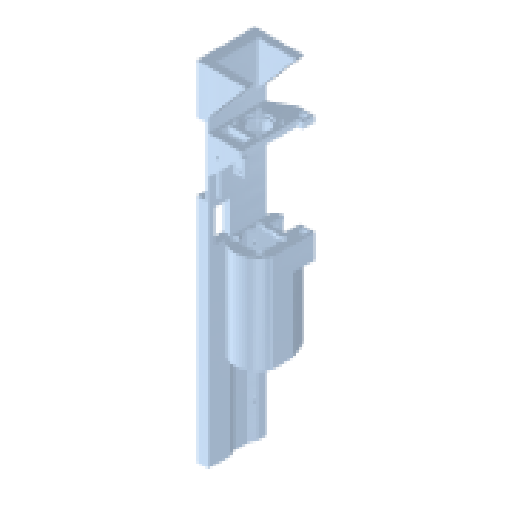
# Autodesk Inventor part: OT2-Pipette V0.7 - frame
Saved by Autodesk Inventor 2025.5 (Build 295498000, 498)
## iProperties
Created: 2026-11-20
Part Number: OT2-Pipette V0.7 - frame
Material: Generisch
Description: printed frame: mount wall with 3 M3 inserts, sleeve + ledge, header window, motor shelf, guide-rod column (PETG/ASA)
Document SubType Name: Modeling
Designer: benir
Density: 1 g/cm^3
Appearance: Light Steel Blue
Author: benir
Autodesk Inventor part; units mm, degrees
ref_plane "WP mount face" through (-9.5, 0, 0) normal (1, 0, 0) x (0, 1, 0)
ref_plane "WP pipette x" through (8.2, 0, 0) normal (1, 0, 0) x (0, 1, 0)
ref_plane "WP pipette z" through (0, 0, -3.46) normal (0, 0, 1) x (1, 0, 0)
ref_plane "WP motor seat" through (0, 123, 0) normal (0, 1, 0) x (-1, 0, 0)
ref_plane "y=ins_top_y" through (0, 46, 0) normal (0, 1, 0) x (-1, 0, 0)
ref_plane "z=ins_z" through (0, 0, 13.25) normal (0, 0, 1) x (1, 0, 0)
ref_plane "z=-ins_z" through (0, 0, -13.25) normal (0, 0, 1) x (1, 0, 0)
ref_plane "y=ins_bot_y" through (0, -43, 0) normal (0, 1, 0) x (-1, 0, 0)
sketch "mount wall" plane through (-9.5, 0, 0) normal (1, 0, 0) x (0, 1, 0)
  line L0 (-66, -18.75) -> (160.35, -18.75)
  line L1 (160.35, -18.75) -> (160.35, 18.75)
  line L2 (160.35, 18.75) -> (-66, 18.75)
  line L3 (-66, 18.75) -> (-66, -18.75)
  line L4 (0, -26.25) -> (0, 26.25) projected
  line L5 (-111.27, 0) -> (205.62, 0) projected
  point P0 (0, 0)
  dimension "d10" = 226.35
  dimension "d11" = 37.5
  dimension "d12" = 66
  dimension "d13" = 18.75
  constraints: 8 end point, 2 parallel, 1 horizontal, 1 perpendicular
  measures "d10" distance of L0.start L0.end
  measures "d11" distance of L2.end L0.start
  measures "d12" horizontal distance of point (0, 0) L2.end
  measures "d13" vertical distance of point (0, 0) L0.start
extrude "Extrusion2" add sketch "mount wall" along normal blind 7.3
fillet "wall top edges" radius 4 2 edges at (-5.85, 160.35, 18.75) (-5.85, 160.35, -18.75)
ref_plane "y=sleeve_y0" through (0, -6, 0) normal (0, 1, 0) x (-1, 0, 0)
sketch "sleeve outline" plane through (0, -6, 0) normal (0, 1, 0) x (-1, 0, 0)
  arc A0 (3.8, -0.6265) -> (-20.2, -0.6265) centre (-8.2, -3.46) ccw construction
  arc A1 (-15.2, -20.71) -> (-1.2, -20.71) centre (-8.2, -9.46) ccw construction
  line L0 (3.8, -0.6265) -> (3.8, -8.63) construction
  line L1 (3.8, -8.63) -> (1.58, -14.21) construction
  line L2 (1.58, -14.21) -> (-1.2, -20.71) construction
  line L3 (-15.2, -20.71) -> (-17.98, -14.21) construction
  line L4 (-17.98, -14.21) -> (-20.2, -8.63) construction
  line L5 (-20.2, -8.63) -> (-20.2, -0.6265) construction
  arc A2 (7.1, -0.2652) -> (-23.5, -0.2652) centre (-8.2, -3.46) ccw
  line L6 (7.1, -0.2652) -> (7.1, -9.2623)
  line L7 (7.1, -9.2623) -> (4.6307, -15.469)
  line L8 (4.6307, -15.469) -> (1.4503, -22.9053)
  arc A3 (-17.8503, -22.9053) -> (1.4503, -22.9053) centre (-8.2, -9.46) ccw
  line L9 (-17.8503, -22.9053) -> (-21.0307, -15.469)
  line L10 (-21.0307, -15.469) -> (-23.5, -9.2623)
  line L11 (-23.5, -9.2623) -> (-23.5, -0.2652)
  point P0 (0, 0)
  dimension "d18" = 3.46
  dimension "d19" = 8.2
  dimension "d20" = 9.46
  dimension "d21" = 8.2
  dimension "d22" = 0.6265
  dimension "d23" = 20.2
  dimension "d24" = 3.8
  dimension "d25" = 20.71
  dimension "d26" = 15.2
  dimension "d27" = 1.2
  dimension "d28" = 8.63
  dimension "d29" = 3.8
  dimension "d30" = 14.21
  dimension "d31" = 1.58
  dimension "d32" = 14.21
  dimension "d33" = 17.98
  dimension "d34" = 8.63
  dimension "d35" = 20.2
  dimension "d36" = 3.3
  constraints: 24 end point, 8 point on circle, 4 centre point, 7 other
  measures "d18" vertical distance of point (0, 0) A0.centre
  measures "d19" horizontal distance of point (0, 0) A0.centre
  measures "d20" vertical distance of point (0, 0) A1.centre
  measures "d21" horizontal distance of point (0, 0) A1.centre
  measures "d22" vertical distance of point (0, 0) L5.end
  measures "d23" horizontal distance of point (0, 0) L5.end
  measures "d24" horizontal distance of point (0, 0) L0.start
  measures "d25" vertical distance of point (0, 0) L3.start
  measures "d26" horizontal distance of point (0, 0) L3.start
  measures "d27" horizontal distance of point (0, 0) L2.end
  measures "d28" vertical distance of point (0, 0) L0.end
  measures "d29" horizontal distance of point (0, 0) L0.end
  measures "d30" vertical distance of point (0, 0) L1.end
  measures "d31" horizontal distance of point (0, 0) L1.end
  measures "d32" vertical distance of point (0, 0) L3.end
  measures "d33" horizontal distance of point (0, 0) L3.end
  measures "d34" vertical distance of point (0, 0) L4.end
  measures "d35" horizontal distance of point (0, 0) L4.end
  measures "d36" distance between parallel lines of L6 L0
extrude "sleeve and ledge" add sketch "sleeve outline" along normal blind 63.5
ref_plane "y=mot_front - shelf_t" through (0, 119, 0) normal (0, 1, 0) x (-1, 0, 0)
sketch "motor shelf" plane through (0, 119, 0) normal (0, 1, 0) x (-1, 0, 0)
  line L0 (2.7, -18.75) -> (-19.2, -18.75)
  line L1 (-19.2, -18.75) -> (-19.2, 18.75)
  line L2 (-19.2, 18.75) -> (2.7, 18.75)
  line L3 (2.7, 18.75) -> (2.7, -18.75)
  line L4 (0, -34.962) -> (0, 27.702) projected
  line L5 (16.1, 0) -> (-30.1, 0) projected
  point P0 (0, 0)
  dimension "d40" = 21.9
  dimension "d41" = 37.5
  dimension "d42" = 2.7
  dimension "d43" = 18.75
  constraints: 8 end point, 2 parallel, 1 horizontal, 1 perpendicular
  measures "d40" distance of L0.start L0.end
  measures "d41" distance of L2.end L0.start
  measures "d42" horizontal distance of point (0, 0) L2.end
  measures "d43" vertical distance of point (0, 0) L0.start
extrude "Extrusion4" add sketch "motor shelf" along normal blind 4
ref_plane "z=-env_z" through (0, 0, -18.75) normal (0, 0, 1) x (1, 0, 0)
sketch "gusset -z" plane through (0, 0, -18.75) normal (0, 0, 1) x (1, 0, 0)
  line L0 (-2.7, 119) -> (19.2, 119)
  line L1 (19.2, 119) -> (-2.7, 97.6)
  line L2 (-2.7, 97.6) -> (-2.7, 119)
  point P0 (0, 0)
  dimension "d47" = 119
  dimension "d48" = 2.7
  dimension "d49" = 119
  dimension "d50" = 19.2
  dimension "d51" = 97.6
  dimension "d52" = 2.7
  constraints: 6 end point
  measures "d47" vertical distance of point (0, 0) L0.start
  measures "d48" horizontal distance of point (0, 0) L0.start
  measures "d49" vertical distance of point (0, 0) L0.end
  measures "d50" horizontal distance of point (0, 0) L0.end
  measures "d51" vertical distance of point (0, 0) L1.end
  measures "d52" horizontal distance of point (0, 0) L1.end
extrude "Extrusion5" add sketch "gusset -z" along normal blind 2.5
ref_plane "z=env_z - gusset_t" through (0, 0, 16.25) normal (0, 0, 1) x (1, 0, 0)
sketch "gusset +z" plane through (0, 0, 16.25) normal (0, 0, 1) x (1, 0, 0)
  line L0 (-2.7, 119) -> (19.2, 119)
  line L1 (19.2, 119) -> (-2.7, 97.6)
  line L2 (-2.7, 97.6) -> (-2.7, 119)
  point P0 (0, 0)
  dimension "d56" = 119
  dimension "d57" = 2.7
  dimension "d58" = 119
  dimension "d59" = 19.2
  dimension "d60" = 97.6
  dimension "d61" = 2.7
  constraints: 6 end point
  measures "d56" vertical distance of point (0, 0) L0.start
  measures "d57" horizontal distance of point (0, 0) L0.start
  measures "d58" vertical distance of point (0, 0) L0.end
  measures "d59" horizontal distance of point (0, 0) L0.end
  measures "d60" vertical distance of point (0, 0) L1.end
  measures "d61" horizontal distance of point (0, 0) L1.end
extrude "Extrusion6" add sketch "gusset +z" along normal blind 2.5
ref_plane "y=col_y0" through (0, 42, 0) normal (0, 1, 0) x (-1, 0, 0)
sketch "rod column" plane through (0, 42, 0) normal (0, 1, 0) x (-1, 0, 0)
  line L0 (-15, -26.5) -> (-23.5, -26.5)
  line L1 (-23.5, -26.5) -> (-23.5, -17)
  line L2 (-23.5, -17) -> (-15, -17)
  line L3 (-15, -17) -> (-15, -26.5)
  line L4 (0, -35.55) -> (0, 27.8) projected
  line L5 (16.1, 0) -> (-30.1, 0) projected
  line L6 (-23.5, -9.2623) -> (-21.0307, -15.469) projected
  line L7 (-21.0307, -15.469) -> (-17.8503, -22.9053) projected
  line L8 (-23.5, -0.2652) -> (-23.5, -9.2623) projected
  line L9 (-23.5, -17) -> (-23.5, -9.2623)
  line L10 (-15, -26.5) -> (-12.404, -25.4672)
  arc A0 (-17.8503, -22.9053) -> (1.4503, -22.9053) centre (-8.2, -9.46) ccw projected
  point P0 (0, 0)
  point P1 (-15, -24.5485)
  point P2 (-20.3759, -17)
  dimension "d66" = 9.5
  dimension "d67" = 15
  dimension "d68" = 26.5
  dimension "d290" = 0
  constraints: 12 end point, 2 parallel, 1 horizontal, 1 perpendicular, 1 point on circle
  measures "d66" distance of L2.end L0.start
  measures "d67" horizontal distance of point (0, 0) L2.end
  measures "d68" vertical distance of point (0, 0) L0.start
  measures "d290" distance between parallel lines of L1 L8
extrude "guide rod column" add sketch "rod column" along normal blind 15.5
ref_plane "y=shelf_y0" through (0, 119, 0) normal (0, 1, 0) x (-1, 0, 0)
sketch "rod boss" plane through (0, 119, 0) normal (0, 1, 0) x (-1, 0, 0)
  line L0 (-14, -26.5) -> (-22.54, -26.5)
  line L1 (-22.54, -26.5) -> (-22.54, -17.75)
  line L2 (-22.54, -17.75) -> (-14, -17.75)
  line L3 (-14, -17.75) -> (-14, -26.5)
  line L4 (0, -35.55) -> (0, 27.8) projected
  line L5 (16.1, 0) -> (-30.1, 0) projected
  line L6 (-19.2, -18.75) -> (2.2, -18.75) projected
  line L7 (-14, -26.5) -> (0, -18.75)
  point P0 (0, 0)
  point P1 (-14, -18.75)
  dimension "d72" = 8.54
  dimension "d73" = 8.75
  dimension "d74" = 14
  dimension "d75" = 26.5
  constraints: 10 end point, 2 parallel, 2 point on line, 1 horizontal, 1 perpendicular
  measures "d72" distance of L0.start L0.end
  measures "d73" distance of L2.end L0.start
  measures "d74" horizontal distance of point (0, 0) L2.end
  measures "d75" vertical distance of point (0, 0) L0.start
extrude "guide rod boss" add sketch "rod boss" along normal blind 4
ref_plane "x=wall_x1 - cut_over" through (-3.2, 0, 0) normal (1, 0, 0) x (0, 1, 0)
sketch "rib" plane through (-3.2, 0, 0) normal (1, 0, 0) x (0, 1, 0)
  line L0 (84, 6.3) -> (119, 6.3)
  line L1 (119, 6.3) -> (119, 13.2)
  line L2 (119, 13.2) -> (84, 13.2)
  line L3 (84, 13.2) -> (84, 6.3)
  line L4 (0, -35.55) -> (0, 27.8) projected
  line L5 (-111.27, 0) -> (205.62, 0) projected
  point P0 (0, 0)
  dimension "d79" = 35
  dimension "d80" = 6.9
  dimension "d81" = 84
  dimension "d82" = 6.3
  constraints: 8 end point, 2 parallel, 1 horizontal, 1 perpendicular
  measures "d79" distance of L0.start L0.end
  measures "d80" distance of L2.end L0.start
  measures "d81" horizontal distance of point (0, 0) L2.end
  measures "d82" vertical distance of point (0, 0) L0.start
extrude "rib behind the top-block relief" add sketch "rib" along normal blind 3.2
ref_plane "y=body_bottom - body_cut_below" through (0, -96, 0) normal (0, 1, 0) x (-1, 0, 0)
sketch "body clearance outline" plane through (0, -96, 0) normal (0, 1, 0) x (-1, 0, 0)
  arc A0 (3.8, -0.6265) -> (-20.2, -0.6265) centre (-8.2, -3.46) ccw construction
  arc A1 (-15.2, -20.71) -> (-1.2, -20.71) centre (-8.2, -9.46) ccw construction
  line L0 (3.8, -0.6265) -> (3.8, -8.63) construction
  line L1 (3.8, -8.63) -> (1.58, -14.21) construction
  line L2 (1.58, -14.21) -> (-1.2, -20.71) construction
  line L3 (-15.2, -20.71) -> (-17.98, -14.21) construction
  line L4 (-17.98, -14.21) -> (-20.2, -8.63) construction
  line L5 (-20.2, -8.63) -> (-20.2, -0.6265) construction
  arc A2 (4.1, -0.5917) -> (-20.5, -0.5917) centre (-8.2, -3.46) ccw
  line L6 (4.1, -0.5917) -> (4.1, -8.6875)
  line L7 (4.1, -8.6875) -> (1.8573, -14.3245)
  line L8 (1.8573, -14.3245) -> (-0.9611, -20.9143)
  arc A3 (-15.4389, -20.9143) -> (-0.9611, -20.9143) centre (-8.2, -9.46) ccw
  line L9 (-15.4389, -20.9143) -> (-18.2573, -14.3245)
  line L10 (-18.2573, -14.3245) -> (-20.5, -8.6875)
  line L11 (-20.5, -8.6875) -> (-20.5, -0.5917)
  point P0 (0, 0)
  dimension "d86" = 3.46
  dimension "d87" = 8.2
  dimension "d88" = 9.46
  dimension "d89" = 8.2
  dimension "d90" = 0.6265
  dimension "d91" = 20.2
  dimension "d92" = 3.8
  dimension "d93" = 20.71
  dimension "d94" = 15.2
  dimension "d95" = 1.2
  dimension "d96" = 8.63
  dimension "d97" = 3.8
  dimension "d98" = 14.21
  dimension "d99" = 1.58
  dimension "d100" = 14.21
  dimension "d101" = 17.98
  dimension "d102" = 8.63
  dimension "d103" = 20.2
  dimension "d104" = 0.3
  constraints: 24 end point, 8 point on circle, 4 centre point, 7 other
  measures "d86" vertical distance of point (0, 0) A0.centre
  measures "d87" horizontal distance of point (0, 0) A0.centre
  measures "d88" vertical distance of point (0, 0) A1.centre
  measures "d89" horizontal distance of point (0, 0) A1.centre
  measures "d90" vertical distance of point (0, 0) L5.end
  measures "d91" horizontal distance of point (0, 0) L5.end
  measures "d92" horizontal distance of point (0, 0) L0.start
  measures "d93" vertical distance of point (0, 0) L3.start
  measures "d94" horizontal distance of point (0, 0) L3.start
  measures "d95" horizontal distance of point (0, 0) L2.end
  measures "d96" vertical distance of point (0, 0) L0.end
  measures "d97" horizontal distance of point (0, 0) L0.end
  measures "d98" vertical distance of point (0, 0) L1.end
  measures "d99" horizontal distance of point (0, 0) L1.end
  measures "d100" vertical distance of point (0, 0) L3.end
  measures "d101" horizontal distance of point (0, 0) L3.end
  measures "d102" vertical distance of point (0, 0) L4.end
  measures "d103" horizontal distance of point (0, 0) L4.end
  measures "d104" distance between parallel lines of L6 L0
extrude "body clearance" cut sketch "body clearance outline" along normal blind 151
ref_plane "y=body_top - cut_over" through (0, 54, 0) normal (0, 1, 0) x (-1, 0, 0)
sketch "knob hole" plane through (0, 54, 0) normal (0, 1, 0) x (-1, 0, 0)
  circle A0 centre (-8.2, -3.46) radius 9.1
  point P0 (0, 0)
  dimension "d108" = 3.46
  dimension "d109" = 8.2
  dimension "d110" = 18.2
  constraints: 1 centre point
  measures "d108" vertical distance of point (0, 0) A0.centre
  measures "d109" horizontal distance of point (0, 0) A0.centre
  measures "d110" diameter of A0
extrude "Extrusion11" cut sketch "knob hole" along normal blind 4.5
ref_plane "y=sleeve_y0 - cut_over" through (0, -7, 0) normal (0, 1, 0) x (-1, 0, 0)
sketch "ejector slot" plane through (0, -7, 0) normal (0, 1, 0) x (-1, 0, 0)
  line L0 (-2.6, -26.5) -> (-13.8, -26.5)
  line L1 (-13.8, -26.5) -> (-13.8, -15.26)
  line L2 (-13.8, -15.26) -> (-2.6, -15.26)
  line L3 (-2.6, -15.26) -> (-2.6, -26.5)
  line L4 (0, -35.55) -> (0, 27.8) projected
  line L5 (16.1, 0) -> (-30.1, 0) projected
  point P0 (0, 0)
  dimension "d114" = 11.2
  dimension "d115" = 11.24
  dimension "d116" = 2.6
  dimension "d117" = 26.5
  constraints: 8 end point, 2 parallel, 1 horizontal, 1 perpendicular
  measures "d114" distance of L0.start L0.end
  measures "d115" distance of L2.end L0.start
  measures "d116" horizontal distance of point (0, 0) L2.end
  measures "d117" vertical distance of point (0, 0) L0.start
extrude "ejector button slot" cut sketch "ejector slot" along normal blind 62
ref_plane "y=body_top - eject_win_h" through (0, 27, 0) normal (0, 1, 0) x (-1, 0, 0)
sketch "eject window" plane through (0, 27, 0) normal (0, 1, 0) x (-1, 0, 0)
  line L0 (-3.2, -26.5) -> (-13.2, -26.5)
  line L1 (-13.2, -26.5) -> (-13.2, -15.46)
  line L2 (-13.2, -15.46) -> (-3.2, -15.46)
  line L3 (-3.2, -15.46) -> (-3.2, -26.5)
  line L4 (0, -35.55) -> (0, 27.8) projected
  line L5 (16.1, 0) -> (-30.1, 0) projected
  point P0 (0, 0)
  dimension "d121" = 10
  dimension "d122" = 11.04
  dimension "d123" = 3.2
  dimension "d124" = 26.5
  constraints: 8 end point, 2 parallel, 1 horizontal, 1 perpendicular
  measures "d121" distance of L0.start L0.end
  measures "d122" distance of L2.end L0.start
  measures "d123" horizontal distance of point (0, 0) L2.end
  measures "d124" vertical distance of point (0, 0) L0.start
extrude "Extrusion13" cut sketch "eject window" along normal blind 31.5
sketch "ledge relief" plane through (0, 54, 0) normal (0, 1, 0) x (-1, 0, 0)
  line L0 (-0.5, -11.96) -> (-15.9, -11.96)
  line L1 (-15.9, -11.96) -> (-15.9, -3.46)
  line L2 (-15.9, -3.46) -> (-0.5, -3.46)
  line L3 (-0.5, -3.46) -> (-0.5, -11.96)
  line L4 (0, -35.55) -> (0, 27.8) projected
  line L5 (16.1, 0) -> (-30.1, 0) projected
  point P0 (0, 0)
  dimension "d127" = 15.4
  dimension "d128" = 8.5
  dimension "d129" = 0.5
  dimension "d130" = 11.96
  constraints: 8 end point, 2 parallel, 1 horizontal, 1 perpendicular
  measures "d127" distance of L0.start L0.end
  measures "d128" distance of L2.end L0.start
  measures "d129" horizontal distance of point (0, 0) L2.end
  measures "d130" vertical distance of point (0, 0) L0.start
extrude "Extrusion14" cut sketch "ledge relief" along normal blind 4.5
ref_plane "y=rod_y0 - 0.5 mm" through (0, 47.5, 0) normal (0, 1, 0) x (-1, 0, 0)
sketch "guide rod hole" plane through (0, 47.5, 0) normal (0, 1, 0) x (-1, 0, 0)
  circle A0 centre (-18.5, -22) radius 2.5
  point P0 (0, 0)
  dimension "d134" = 22
  dimension "d135" = 18.5
  dimension "d136" = 5
  constraints: 1 centre point
  measures "d134" vertical distance of point (0, 0) A0.centre
  measures "d135" horizontal distance of point (0, 0) A0.centre
  measures "d136" diameter of A0
extrude "Extrusion15" cut sketch "guide rod hole" along normal blind 76.5
ref_plane "y=body_bottom - cut_over" through (0, -67, 0) normal (0, 1, 0) x (-1, 0, 0)
sketch "seat insert holes" plane through (0, -67, 0) normal (0, 1, 0) x (-1, 0, 0)
  circle A0 centre (5.85, 13.5) radius 2.05
  circle A1 centre (5.85, -16) radius 2.05
  point P0 (0, 0)
  dimension "d140" = 13.5
  dimension "d141" = 5.85
  dimension "d142" = 4.1
  dimension "d143" = 16
  dimension "d144" = 5.85
  dimension "d145" = 4.1
  constraints: 2 centre point
  measures "d140" vertical distance of point (0, 0) A0.centre
  measures "d141" horizontal distance of point (0, 0) A0.centre
  measures "d142" diameter of A0
  measures "d143" vertical distance of point (0, 0) A1.centre
  measures "d144" horizontal distance of point (0, 0) A1.centre
  measures "d145" diameter of A1
extrude "M3 inserts for the pipette seat" cut sketch "seat insert holes" along normal blind 6.7
ref_plane "x=mount_x - cut_over" through (-10.5, 0, 0) normal (1, 0, 0) x (0, 1, 0)
sketch "insert holes" plane through (-10.5, 0, 0) normal (1, 0, 0) x (0, 1, 0)
  circle A0 centre (46, 13.25) radius 2.05
  circle A1 centre (46, -13.25) radius 2.05
  circle A2 centre (-43, -13.25) radius 2.05
  point P0 (0, 0)
  dimension "d149" = 13.25
  dimension "d150" = 46
  dimension "d151" = 4.1
  dimension "d152" = 13.25
  dimension "d153" = 46
  dimension "d154" = 4.1
  dimension "d155" = 13.25
  dimension "d156" = 43
  dimension "d157" = 4.1
  constraints: 3 centre point
  measures "d149" vertical distance of point (0, 0) A0.centre
  measures "d150" horizontal distance of point (0, 0) A0.centre
  measures "d151" diameter of A0
  measures "d152" vertical distance of point (0, 0) A1.centre
  measures "d153" horizontal distance of point (0, 0) A1.centre
  measures "d154" diameter of A1
  measures "d155" vertical distance of point (0, 0) A2.centre
  measures "d156" horizontal distance of point (0, 0) A2.centre
  measures "d157" diameter of A2
extrude "Extrusion17" cut sketch "insert holes" along normal blind 7.7
sketch "insert recesses" plane through (-10.5, 0, 0) normal (1, 0, 0) x (0, 1, 0)
  circle A0 centre (46, 13.25) radius 3
  circle A1 centre (46, -13.25) radius 3
  circle A2 centre (-43, -13.25) radius 3
  point P0 (0, 0)
  dimension "d160" = 13.25
  dimension "d161" = 46
  dimension "d162" = 6
  dimension "d163" = 13.25
  dimension "d164" = 46
  dimension "d165" = 6
  dimension "d166" = 13.25
  dimension "d167" = 43
  dimension "d168" = 6
  constraints: 3 centre point
  measures "d160" vertical distance of point (0, 0) A0.centre
  measures "d161" horizontal distance of point (0, 0) A0.centre
  measures "d162" diameter of A0
  measures "d163" vertical distance of point (0, 0) A1.centre
  measures "d164" horizontal distance of point (0, 0) A1.centre
  measures "d165" diameter of A1
  measures "d166" vertical distance of point (0, 0) A2.centre
  measures "d167" horizontal distance of point (0, 0) A2.centre
  measures "d168" diameter of A2
extrude "Extrusion18" cut sketch "insert recesses" along normal blind 1.3
sketch "grub screw holes" plane through (-10.5, 0, 0) normal (1, 0, 0) x (0, 1, 0)
  circle A0 centre (4, -3.46) radius 1.25
  circle A1 centre (42, -3.46) radius 1.25
  point P0 (0, 0)
  dimension "d171" = 3.46
  dimension "d172" = 4
  dimension "d173" = 2.5
  dimension "d174" = 3.46
  dimension "d175" = 42
  dimension "d176" = 2.5
  constraints: 2 centre point
  measures "d171" vertical distance of point (0, 0) A0.centre
  measures "d172" horizontal distance of point (0, 0) A0.centre
  measures "d173" diameter of A0
  measures "d174" vertical distance of point (0, 0) A1.centre
  measures "d175" horizontal distance of point (0, 0) A1.centre
  measures "d176" diameter of A1
extrude "M3 grub screw holes" cut sketch "grub screw holes" along normal blind 7.7
ref_plane "y=mot_front - mot_pilot_h - pilot_clr" through (0, 121.1, 0) normal (0, 1, 0) x (-1, 0, 0)
sketch "motor pilot recess" plane through (0, 121.1, 0) normal (0, 1, 0) x (-1, 0, 0)
  circle A0 centre (-8.2, -3.46) radius 8.2
  point P0 (0, 0)
  dimension "d180" = 3.46
  dimension "d181" = 8.2
  dimension "d182" = 16.4
  constraints: 1 centre point
  measures "d180" vertical distance of point (0, 0) A0.centre
  measures "d181" horizontal distance of point (0, 0) A0.centre
  measures "d182" diameter of A0
extrude "Extrusion20" cut sketch "motor pilot recess" along normal blind 2.9
ref_plane "y=mot_front - shelf_t - cut_over" through (0, 118, 0) normal (0, 1, 0) x (-1, 0, 0)
sketch "motor boss hole" plane through (0, 118, 0) normal (0, 1, 0) x (-1, 0, 0)
  circle A0 centre (-8.2, -3.46) radius 6.9
  point P0 (0, 0)
  dimension "d186" = 3.46
  dimension "d187" = 8.2
  dimension "d188" = 13.8
  constraints: 1 centre point
  measures "d186" vertical distance of point (0, 0) A0.centre
  measures "d187" horizontal distance of point (0, 0) A0.centre
  measures "d188" diameter of A0
extrude "Extrusion21" cut sketch "motor boss hole" along normal blind 6
sketch "motor screw holes" plane through (0, 118, 0) normal (0, 1, 0) x (-1, 0, 0)
  circle A0 centre (-0.5, -11.16) radius 1.2
  circle A1 centre (-0.5, 4.24) radius 1.2
  circle A2 centre (-15.9, -11.16) radius 1.2
  circle A3 centre (-15.9, 4.24) radius 1.2
  point P0 (0, 0)
  dimension "d191" = 11.16
  dimension "d192" = 0.5
  dimension "d193" = 2.4
  dimension "d194" = 4.24
  dimension "d195" = 0.5
  dimension "d196" = 2.4
  dimension "d197" = 11.16
  dimension "d198" = 15.9
  dimension "d199" = 2.4
  dimension "d200" = 4.24
  dimension "d201" = 15.9
  dimension "d202" = 2.4
  constraints: 4 centre point
  measures "d191" vertical distance of point (0, 0) A0.centre
  measures "d192" horizontal distance of point (0, 0) A0.centre
  measures "d193" diameter of A0
  measures "d194" vertical distance of point (0, 0) A1.centre
  measures "d195" horizontal distance of point (0, 0) A1.centre
  measures "d196" diameter of A1
  measures "d197" vertical distance of point (0, 0) A2.centre
  measures "d198" horizontal distance of point (0, 0) A2.centre
  measures "d199" diameter of A2
  measures "d200" vertical distance of point (0, 0) A3.centre
  measures "d201" horizontal distance of point (0, 0) A3.centre
  measures "d202" diameter of A3
extrude "4 x M2 motor screw holes" cut sketch "motor screw holes" along normal blind 6
sketch "screwdriver channels" plane through (0, 54, 0) normal (0, 1, 0) x (-1, 0, 0)
  circle A0 centre (-0.5, -11.16) radius 2.2
  circle A1 centre (-0.5, 4.24) radius 2.2
  circle A2 centre (-15.9, -11.16) radius 2.2
  circle A3 centre (-15.9, 4.24) radius 2.2
  point P0 (0, 0)
  dimension "d205" = 11.16
  dimension "d206" = 0.5
  dimension "d207" = 4.4
  dimension "d208" = 4.24
  dimension "d209" = 0.5
  dimension "d210" = 4.4
  dimension "d211" = 11.16
  dimension "d212" = 15.9
  dimension "d213" = 4.4
  dimension "d214" = 4.24
  dimension "d215" = 15.9
  dimension "d216" = 4.4
  constraints: 4 centre point
  measures "d205" vertical distance of point (0, 0) A0.centre
  measures "d206" horizontal distance of point (0, 0) A0.centre
  measures "d207" diameter of A0
  measures "d208" vertical distance of point (0, 0) A1.centre
  measures "d209" horizontal distance of point (0, 0) A1.centre
  measures "d210" diameter of A1
  measures "d211" vertical distance of point (0, 0) A2.centre
  measures "d212" horizontal distance of point (0, 0) A2.centre
  measures "d213" diameter of A2
  measures "d214" vertical distance of point (0, 0) A3.centre
  measures "d215" horizontal distance of point (0, 0) A3.centre
  measures "d216" diameter of A3
extrude "Extrusion23" cut sketch "screwdriver channels" along normal blind 66
sketch "plug pocket" plane through (-10.5, 0, 0) normal (1, 0, 0) x (0, 1, 0)
  line L0 (54, 1) -> (83, 1)
  line L1 (83, 1) -> (83, 17.6)
  line L2 (83, 17.6) -> (54, 17.6)
  line L3 (54, 17.6) -> (54, 1)
  line L4 (0, -35.55) -> (0, 27.8) projected
  line L5 (-111.27, 0) -> (205.62, 0) projected
  point P0 (0, 0)
  dimension "d219" = 29
  dimension "d220" = 16.6
  dimension "d221" = 54
  dimension "d222" = 1
  constraints: 8 end point, 2 parallel, 1 horizontal, 1 perpendicular
  measures "d219" distance of L0.start L0.end
  measures "d220" distance of L2.end L0.start
  measures "d221" horizontal distance of point (0, 0) L2.end
  measures "d222" vertical distance of point (0, 0) L0.start
extrude "pocket for the robot's plug holder" cut sketch "plug pocket" along normal blind 3.5
sketch "header window" plane through (-10.5, 0, 0) normal (1, 0, 0) x (0, 1, 0)
  line L0 (57.9, 4.45) -> (79.1, 4.45)
  line L1 (79.1, 4.45) -> (79.1, 14.15)
  line L2 (79.1, 14.15) -> (57.9, 14.15)
  line L3 (57.9, 14.15) -> (57.9, 4.45)
  line L4 (0, -35.55) -> (0, 27.8) projected
  line L5 (-111.27, 0) -> (205.62, 0) projected
  point P0 (0, 0)
  dimension "d225" = 21.2
  dimension "d226" = 9.7
  dimension "d227" = 57.9
  dimension "d228" = 4.45
  constraints: 8 end point, 2 parallel, 1 horizontal, 1 perpendicular
  measures "d225" distance of L0.start L0.end
  measures "d226" distance of L2.end L0.start
  measures "d227" horizontal distance of point (0, 0) L2.end
  measures "d228" vertical distance of point (0, 0) L0.start
extrude "2x5 header window" cut sketch "header window" along normal blind 9.3
ref_plane "z=brd_z_front" through (0, 0, 15.35) normal (0, 0, 1) x (1, 0, 0)
sketch "XIAO pin clearance" plane through (0, 0, 15.35) normal (0, 0, 1) x (1, 0, 0)
  line L0 (-0.2, 88.5) -> (22.8, 88.5)
  line L1 (22.8, 88.5) -> (22.8, 109.5)
  line L2 (22.8, 109.5) -> (-0.2, 109.5)
  line L3 (-0.2, 109.5) -> (-0.2, 88.5)
  line L4 (0, -111.27) -> (0, 205.62) projected
  line L5 (-16.1, 0) -> (30.1, 0) projected
  point P0 (0, 0)
  dimension "d238" = 23
  dimension "d239" = 21
  dimension "d240" = 0.2
  dimension "d241" = 88.5
  constraints: 8 end point, 2 parallel, 1 horizontal, 1 perpendicular
  measures "d238" distance of L0.start L0.end
  measures "d239" distance of L2.end L0.start
  measures "d240" horizontal distance of point (0, 0) L2.end
  measures "d241" vertical distance of point (0, 0) L0.start
extrude "Extrusion27" cut sketch "XIAO pin clearance" along normal blind 1.8
sketch "board tabs" plane through (0, 0, 15.35) normal (0, 0, 1) x (1, 0, 0)
  line L0 (14.8, 108.8) -> (20.8, 108.8)
  line L1 (20.8, 108.8) -> (20.8, 119.5)
  line L2 (20.8, 119.5) -> (14.8, 119.5)
  line L3 (14.8, 119.5) -> (14.8, 108.8)
  line L4 (0, -111.27) -> (0, 205.62) projected
  line L5 (-16.1, 0) -> (30.1, 0) projected
  line L6 (1.2, 108.8) -> (7.2, 108.8)
  line L7 (7.2, 108.8) -> (7.2, 119.5)
  line L8 (7.2, 119.5) -> (1.2, 119.5)
  line L9 (1.2, 119.5) -> (1.2, 108.8)
  point P0 (0, 0)
  dimension "d244" = 6
  dimension "d245" = 10.7
  dimension "d246" = 14.8
  dimension "d247" = 108.8
  dimension "d248" = 6
  dimension "d249" = 10.7
  dimension "d250" = 1.2
  dimension "d251" = 108.8
  constraints: 16 end point, 4 parallel, 2 horizontal, 2 perpendicular
  measures "d244" distance of L0.start L0.end
  measures "d245" distance of L2.end L0.start
  measures "d246" horizontal distance of point (0, 0) L2.end
  measures "d247" vertical distance of point (0, 0) L0.start
  measures "d248" distance of L6.start L6.end
  measures "d249" distance of L8.end L6.start
  measures "d250" horizontal distance of point (0, 0) L8.end
  measures "d251" vertical distance of point (0, 0) L6.start
extrude "Extrusion28" add sketch "board tabs" along normal blind 3.4
ref_plane "z=brd_z_front - cut_over" through (0, 0, 14.35) normal (0, 0, 1) x (1, 0, 0)
sketch "board screw holes" plane through (0, 0, 14.35) normal (0, 0, 1) x (1, 0, 0)
  circle A0 centre (17.8, 111.8) radius 0.9
  circle A1 centre (4.2, 111.8) radius 0.9
  point P0 (0, 0)
  dimension "d255" = 111.8
  dimension "d256" = 17.8
  dimension "d257" = 1.8
  dimension "d258" = 111.8
  dimension "d259" = 4.2
  dimension "d260" = 1.8
  constraints: 2 centre point
  measures "d255" vertical distance of point (0, 0) A0.centre
  measures "d256" horizontal distance of point (0, 0) A0.centre
  measures "d257" diameter of A0
  measures "d258" vertical distance of point (0, 0) A1.centre
  measures "d259" horizontal distance of point (0, 0) A1.centre
  measures "d260" diameter of A1
extrude "tool board M2 holes" cut sketch "board screw holes" along normal blind 5.4
ref_plane "x=wall_x1 + cut_over" through (-1.2, 0, 0) normal (1, 0, 0) x (0, 1, 0)
sketch "switch screw holes" plane through (-1.2, 0, 0) normal (1, 0, 0) x (0, 1, 0)
  circle A0 centre (111.3, -12.85) radius 0.9
  circle A1 centre (111.3, -6.35) radius 0.9
  point P0 (0, 0)
  dimension "d264" = 12.85
  dimension "d265" = 111.3
  dimension "d266" = 1.8
  dimension "d267" = 6.35
  dimension "d268" = 111.3
  dimension "d269" = 1.8
  constraints: 2 centre point
  measures "d264" vertical distance of point (0, 0) A0.centre
  measures "d265" horizontal distance of point (0, 0) A0.centre
  measures "d266" diameter of A0
  measures "d267" vertical distance of point (0, 0) A1.centre
  measures "d268" horizontal distance of point (0, 0) A1.centre
  measures "d269" diameter of A1
extrude "Extrusion30" cut sketch "switch screw holes" against normal blind 7
sketch "GEN2 outline trim" plane through (0, -67, 0) normal (0, 1, 0) x (-1, 0, 0)
  line L0 (59.5, -75.5) -> (-72.84, -75.5)
  line L1 (-72.84, -75.5) -> (-72.84, 68.75)
  line L2 (-72.84, 68.75) -> (59.5, 68.75)
  line L3 (59.5, 68.75) -> (59.5, -75.5)
  line L4 (0, -104.35) -> (0, 97.6) projected
  line L5 (85.968, 0) -> (-99.308, 0) projected
  line L6 (9.5, -25.5) -> (-22.84, -25.5)
  line L7 (-22.84, -25.5) -> (-22.84, 18.75)
  line L8 (-22.84, 18.75) -> (9.5, 18.75)
  line L9 (9.5, 18.75) -> (9.5, -25.5)
  point P0 (0, 0)
  dimension "d272" = 132.34
  dimension "d273" = 144.25
  dimension "d274" = 59.5
  dimension "d275" = 75.5
  dimension "d276" = 32.34
  dimension "d277" = 44.25
  dimension "d278" = 9.5
  dimension "d279" = 25.5
  constraints: 16 end point, 4 parallel, 2 horizontal, 2 perpendicular
  measures "d272" distance of L0.start L0.end
  measures "d273" distance of L2.end L0.start
  measures "d274" horizontal distance of point (0, 0) L2.end
  measures "d275" vertical distance of point (0, 0) L0.start
  measures "d276" distance of L6.start L6.end
  measures "d277" distance of L8.end L6.start
  measures "d278" horizontal distance of point (0, 0) L8.end
  measures "d279" vertical distance of point (0, 0) L6.start
extrude "trim to the GEN2 outline" cut sketch "GEN2 outline trim" along normal through all both and the other way through all contours L0 L4 L6 L9 L5 L3 | L0 L1 L5 L7 L6 L4 | L5 L9 L8 L4 L2 L3 | L1 L2 L4 L8 L7 L5
sketch "Sketch32" plane through (-2.2, -66, -18.75) normal (0, 0, -1) x (-1, 0, 0)
  line L0 (7.3, 226.35) -> (7.3, 222.35) projected
  line L1 (7.3, 226.35) -> (7.3, 189)
  line L2 (7.3, 0) -> (7.3, 222.35) projected
  line L3 (7.3, 189) -> (-24.74, 226.35)
  line L4 (-24.74, 226.35) -> (7.3, 226.35)
  line L5 (-24.74, 185) -> (-24.74, 189) projected
  point P0 (-2.2, 66)
  point P1 (-24.74, 187)
  point P2 (0, 189)
  constraints: 6 end point, 1 horizontal alignment, 1 midpoint, 1 perpendicular, 1 point on line, 1 vertical alignment
extrude "Extrusion32" add sketch "Sketch32" against normal blind 5
mirror "Mirror1" about plane through (0, 0, 0) normal (0, 0, 1) of "Extrusion32"
sketch "top-block relief" plane through (-10.5, 0, 0) normal (1, 0, 0) x (0, 1, 0)
  line L0 (84, -5) -> (128, -5)
  line L1 (128, -5) -> (128, 19.75)
  line L2 (128, 19.75) -> (84, 19.75)
  line L3 (84, 19.75) -> (84, -5)
  line L4 (0, -35.75) -> (0, 29) projected
  line L5 (-111.27, 0) -> (205.62, 0) projected
  point P0 (0, 0)
  dimension "d231" = 44
  dimension "d232" = 24.75
  dimension "d233" = 84
  dimension "d234" = 5
  constraints: 8 end point, 2 parallel, 1 horizontal, 1 perpendicular
  measures "d231" distance of L0.start L0.end
  measures "d232" distance of L2.end L0.start
  measures "d233" horizontal distance of point (0, 0) L2.end
  measures "d234" vertical distance of point (0, 0) L0.start
extrude "relief for the mount's top block" cut sketch "top-block relief" along normal blind 6.5
sketch "Sketch33" plane through (0, 119, 0) normal (0, -1, 0) x (1, 0, 0)
  line L0 (-2.2, 13.75) -> (-2.2, 18.75) projected
  line L1 (-2.2, 13.75) -> (22.54, 13.75) projected
  line L2 (22.54, 18.75) -> (22.54, 13.75) projected
  line L3 (22.54, 18.75) -> (-2.2, 18.75) projected
  line L4 (19.2, -16.25) -> (19.2, 15.35) projected
  line L5 (0, 13.2) -> (0, 6.3824) projected
  line L6 (15, 13.75) -> (0, 13.75)
  line L7 (0, 13.75) -> (0, 7.75)
  line L8 (0, 7.75) -> (15, 7.75)
  line L9 (15, 7.75) -> (15, 13.75)
  point P0 (0, 0)
  dimension "d286" = 6
  dimension "d287" = 15
  constraints: 8 end point, 2 parallel, 2 point on line, 1 horizontal, 1 perpendicular
  measures "d286" distance between parallel lines of L6 L8
  measures "d287" distance between parallel lines of L5 L9
extrude "Extrusion33" cut sketch "Sketch33" against normal up to surface (4 mm away) contours L1 L9 L8 L5 L7
equation "\"d10\" = mot_rear - body_bottom"
equation "\"d11\" = 2 * env_z"
equation "\"d12\" = -body_bottom"
equation "\"d13\" = env_z"
equation "\"d14\" = wall_x1 - mount_x"
equation "\"d16\" = wall_fillet"
equation "\"d18\" = -pip_z"
equation "\"d19\" = pip_x"
equation "\"d20\" = nose_c - pip_z"
equation "\"d21\" = pip_x"
equation "\"d23\" = pip_x + body_hw"
equation "\"d24\" = body_hw - pip_x"
equation "\"d26\" = pip_x + nose_hw"
equation "\"d27\" = pip_x - nose_hw"
equation "\"d28\" = body_flat_d - pip_z"
equation "\"d29\" = body_hw - pip_x"
equation "\"d30\" = body_ch_d - pip_z"
equation "\"d31\" = body_ch_w - pip_x"
equation "\"d32\" = body_ch_d - pip_z"
equation "\"d33\" = pip_x + body_ch_w"
equation "\"d34\" = body_flat_d - pip_z"
equation "\"d35\" = pip_x + body_hw"
equation "\"d36\" = wall_out"
equation "\"d37\" = ledge_t + body_top - sleeve_y0"
equation "\"d40\" = shelf_x1 + shelf_back - wall_x1"
equation "\"d41\" = 2 * env_z"
equation "\"d42\" = shelf_back - wall_x1"
equation "\"d43\" = env_z"
equation "\"d44\" = shelf_t"
equation "\"d47\" = mot_front - shelf_t"
equation "\"d48\" = shelf_back - wall_x1"
equation "\"d49\" = mot_front - shelf_t"
equation "\"d50\" = shelf_x1"
equation "\"d51\" = -shelf_t + mot_front - gusset_h"
equation "\"d52\" = shelf_back - wall_x1"
equation "\"d53\" = gusset_t"
equation "\"d56\" = mot_front - shelf_t"
equation "\"d57\" = shelf_back - wall_x1"
equation "\"d58\" = mot_front - shelf_t"
equation "\"d59\" = shelf_x1"
equation "\"d60\" = -shelf_t + mot_front - gusset_h"
equation "\"d61\" = shelf_back - wall_x1"
equation "\"d62\" = gusset_t"
equation "\"d66\" = col_front + rod_z + cut_over + env_zr"
equation "\"d67\" = rod_x - col_hw"
equation "\"d68\" = cut_over + env_zr"
equation "\"d69\" = col_y1 - col_y0"
equation "\"d72\" = -env_margin + env_x1 + boss_hw - rod_x"
equation "\"d73\" = 2 * cut_over - env_z + env_zr"
equation "\"d74\" = rod_x - boss_hw"
equation "\"d75\" = cut_over + env_zr"
equation "\"d76\" = shelf_t"
equation "\"d79\" = shelf_y0 - relief_y0"
equation "\"d80\" = rib_z1 - rib_z0"
equation "\"d81\" = relief_y0"
equation "\"d82\" = rib_z0"
equation "\"d83\" = -wall_x1 + rib_x1 + cut_over"
equation "\"d86\" = -pip_z"
equation "\"d87\" = pip_x"
equation "\"d88\" = nose_c - pip_z"
equation "\"d89\" = pip_x"
equation "\"d91\" = pip_x + body_hw"
equation "\"d92\" = body_hw - pip_x"
equation "\"d94\" = pip_x + nose_hw"
equation "\"d95\" = pip_x - nose_hw"
equation "\"d96\" = body_flat_d - pip_z"
equation "\"d97\" = body_hw - pip_x"
equation "\"d98\" = body_ch_d - pip_z"
equation "\"d99\" = body_ch_w - pip_x"
equation "\"d100\" = body_ch_d - pip_z"
equation "\"d101\" = pip_x + body_ch_w"
equation "\"d102\" = body_flat_d - pip_z"
equation "\"d103\" = pip_x + body_hw"
equation "\"d104\" = clr"
equation "\"d105\" = body_len + body_cut_below"
equation "\"d108\" = -pip_z"
equation "\"d109\" = pip_x"
equation "\"d110\" = knob_hole_d"
equation "\"d111\" = ledge_t + 2 * cut_over"
equation "\"d114\" = 2 * ej_slot_clr + 0 * pip_x + 2 * ej_hw"
equation "\"d115\" = ej_slot_z + pip_z - ej_d0 + cut_over + env_zr"
equation "\"d116\" = -ej_hw + pip_x - ej_slot_clr"
equation "\"d117\" = cut_over + env_zr"
equation "\"d118\" = -sleeve_y0 + body_top + cut_over"
equation "\"d121\" = 2 * eject_win_hw + 0 * pip_x"
equation "\"d122\" = -eject_win_d + pip_z + cut_over + env_zr"
equation "\"d123\" = pip_x - eject_win_hw"
equation "\"d124\" = cut_over + env_zr"
equation "\"d125\" = ledge_t + eject_win_h + cut_over"
equation "\"d127\" = mot_holes + 0 * pip_x"
equation "\"d128\" = 0 * pip_z + ledge_relief_d"
equation "\"d129\" = pip_x - 0.5 * mot_holes"
equation "\"d130\" = ledge_relief_d - pip_z"
equation "\"d131\" = ledge_t + 2 * cut_over"
equation "\"d134\" = -rod_z"
equation "\"d135\" = rod_x"
equation "\"d140\" = seat_screw_z1"
equation "\"d141\" = -seat_screw_x"
equation "\"d142\" = seat_ins_d"
equation "\"d143\" = -seat_screw_z2"
equation "\"d144\" = -seat_screw_x"
equation "\"d145\" = seat_ins_d"
equation "\"d146\" = seat_ins_h + cut_over"
equation "\"d149\" = ins_z"
equation "\"d150\" = ins_top_y"
equation "\"d151\" = insert_d"
equation "\"d152\" = ins_z"
equation "\"d153\" = ins_top_y"
equation "\"d154\" = insert_d"
equation "\"d155\" = ins_z"
equation "\"d156\" = -ins_bot_y"
equation "\"d157\" = insert_d"
equation "\"d158\" = -mount_x + insert_x_end + cut_over"
equation "\"d160\" = ins_z"
equation "\"d161\" = ins_top_y"
equation "\"d162\" = insert_cb_d"
equation "\"d163\" = ins_z"
equation "\"d164\" = ins_top_y"
equation "\"d165\" = insert_cb_d"
equation "\"d166\" = ins_z"
equation "\"d167\" = -ins_bot_y"
equation "\"d168\" = insert_cb_d"
equation "\"d169\" = insert_cb_h + cut_over"
equation "\"d171\" = -pip_z"
equation "\"d172\" = body_bottom + grub_y1"
equation "\"d173\" = grub_d"
equation "\"d174\" = -pip_z"
equation "\"d175\" = body_bottom + grub_y2"
equation "\"d176\" = grub_d"
equation "\"d177\" = -mount_x - body_hw + pip_x + grub_into + cut_over"
equation "\"d180\" = -pip_z"
equation "\"d181\" = pip_x"
equation "\"d182\" = mot_pilot_d + pilot_clr"
equation "\"d183\" = pilot_clr + mot_pilot_h + cut_over"
equation "\"d186\" = -pip_z"
equation "\"d187\" = pip_x"
equation "\"d188\" = mot_boss_d + boss_clr"
equation "\"d189\" = shelf_t + 2 * cut_over"
equation "\"d191\" = 0.5 * mot_holes - pip_z"
equation "\"d192\" = pip_x - 0.5 * mot_holes"
equation "\"d193\" = m2_clear_d"
equation "\"d194\" = pip_z + 0.5 * mot_holes"
equation "\"d195\" = pip_x - 0.5 * mot_holes"
equation "\"d196\" = m2_clear_d"
equation "\"d197\" = 0.5 * mot_holes - pip_z"
equation "\"d198\" = pip_x + 0.5 * mot_holes"
equation "\"d199\" = m2_clear_d"
equation "\"d200\" = pip_z + 0.5 * mot_holes"
equation "\"d201\" = pip_x + 0.5 * mot_holes"
equation "\"d202\" = m2_clear_d"
equation "\"d203\" = shelf_t + 2 * cut_over"
equation "\"d205\" = 0.5 * mot_holes - pip_z"
equation "\"d206\" = pip_x - 0.5 * mot_holes"
equation "\"d207\" = driver_d"
equation "\"d208\" = pip_z + 0.5 * mot_holes"
equation "\"d209\" = pip_x - 0.5 * mot_holes"
equation "\"d210\" = driver_d"
equation "\"d211\" = 0.5 * mot_holes - pip_z"
equation "\"d212\" = pip_x + 0.5 * mot_holes"
equation "\"d213\" = driver_d"
equation "\"d214\" = pip_z + 0.5 * mot_holes"
equation "\"d215\" = pip_x + 0.5 * mot_holes"
equation "\"d216\" = driver_d"
equation "\"d217\" = -body_top + mot_front - shelf_t + 2 * cut_over"
equation "\"d219\" = plug_pocket_l + 0 * hdr_y"
equation "\"d220\" = plug_pocket_w + 0 * hdr_z"
equation "\"d221\" = hdr_y - 0.5 * plug_pocket_l"
equation "\"d222\" = hdr_z - 0.5 * plug_pocket_w"
equation "\"d223\" = plug_pocket_d + cut_over"
equation "\"d225\" = hdr_l + 0 * hdr_y"
equation "\"d226\" = hdr_w + 0 * hdr_z"
equation "\"d227\" = hdr_y - 0.5 * hdr_l"
equation "\"d228\" = hdr_z - 0.5 * hdr_w"
equation "\"d229\" = -mount_x + wall_x1 + 2 * cut_over"
equation "\"d239\" = brd_xiao_y1 - brd_xiao_y0"
equation "\"d241\" = brd_xiao_y0"
equation "\"d242\" = brd_back_clr"
equation "\"d244\" = brd_tab_w + 0 * brd_hole_x1"
equation "\"d246\" = brd_hole_x1 - 0.5 * brd_tab_w"
equation "\"d247\" = brd_hole_y - brd_tab_below"
equation "\"d248\" = brd_tab_w + 0 * brd_hole_x2"
equation "\"d250\" = brd_hole_x2 - 0.5 * brd_tab_w"
equation "\"d251\" = brd_hole_y - brd_tab_below"
equation "\"d252\" = env_z - brd_z_front"
equation "\"d255\" = brd_hole_y"
equation "\"d256\" = brd_hole_x1"
equation "\"d257\" = brd_pilot_d"
equation "\"d258\" = brd_hole_y"
equation "\"d259\" = brd_hole_x2"
equation "\"d260\" = brd_pilot_d"
equation "\"d261\" = -brd_z_front + env_z + 2 * cut_over"
equation "\"d264\" = 0.5 * sw_pitch - 0.5 * sw_l - sw_z0"
equation "\"d265\" = sw_h + sw_y0 - sw_hole_down"
equation "\"d266\" = sw_pilot_d"
equation "\"d267\" = -0.5 * sw_pitch - 0.5 * sw_l - sw_z0"
equation "\"d268\" = sw_h + sw_y0 - sw_hole_down"
equation "\"d269\" = sw_pilot_d"
equation "\"d270\" = hole_depth + cut_over"
equation "\"d276\" = env_x1 - mount_x"
equation "\"d277\" = env_z + env_zr"
equation "\"d278\" = -mount_x"
equation "\"d279\" = env_zr"
equation "\"d231\" = relief_y1 - relief_y0"
equation "\"d232\" = cut_over + env_z - relief_z0"
equation "\"d233\" = relief_y0"
equation "\"d234\" = -relief_z0"
equation "\"d235\" = relief_d + cut_over"
equation "\"mot_rear\" = 160.35"
equation "\"body_bottom\" = -66"
equation "\"env_z\" = 18.75"
equation "\"wall_x1\" = -2.2"
equation "\"mount_x\" = -9.5"
equation "\"wall_fillet\" = 4"
equation "\"wall_out\" = 3.3"
equation "\"ledge_t\" = 2.5"
equation "\"body_top\" = 55"
equation "\"sleeve_y0\" = -6"
equation "\"shelf_x1\" = 19.2"
equation "\"shelf_back\" = 0.5"
equation "\"shelf_t\" = 4"
equation "\"gusset_t\" = 2.5"
equation "\"col_front\" = 5"
equation "\"rod_z\" = -22"
equation "\"cut_over\" = 1"
equation "\"env_zr\" = 25.5"
equation "\"col_y1\" = 57.5"
equation "\"col_y0\" = 42"
equation "\"env_margin\" = 0.3"
equation "\"env_x1\" = 22.84"
equation "\"boss_hw\" = 4.5"
equation "\"rod_x\" = 18.5"
equation "\"shelf_y0\" = 119"
equation "\"relief_y0\" = 84"
equation "\"rib_z1\" = 13.2"
equation "\"rib_z0\" = 6.3"
equation "\"rib_x1\" = 0"
equation "\"clr\" = 0.3"
equation "\"body_len\" = 121"
equation "\"body_cut_below\" = 30"
equation "\"knob_hole_d\" = 18.2"
equation "\"ej_slot_clr\" = 0.6"
equation "\"pip_x\" = 8.2"
equation "\"ej_hw\" = 5"
equation "\"ej_slot_z\" = 0.5"
equation "\"pip_z\" = -3.46"
equation "\"ej_d0\" = 12.3"
equation "\"eject_win_hw\" = 5"
equation "\"eject_win_d\" = 12"
equation "\"eject_win_h\" = 28"
equation "\"mot_holes\" = 15.4"
equation "\"ledge_relief_d\" = 8.5"
equation "\"seat_ins_d\" = 4.1"
equation "\"seat_ins_h\" = 5.7"
equation "\"insert_d\" = 4.1"
equation "\"insert_x_end\" = -2.8"
equation "\"insert_cb_d\" = 6"
equation "\"insert_cb_h\" = 0.3"
equation "\"grub_d\" = 2.5"
equation "\"body_hw\" = 12"
equation "\"grub_into\" = 1"
equation "\"mot_pilot_d\" = 16"
equation "\"pilot_clr\" = 0.4"
equation "\"mot_pilot_h\" = 1.5"
equation "\"mot_boss_d\" = 13"
equation "\"boss_clr\" = 0.8"
equation "\"m2_clear_d\" = 2.4"
equation "\"driver_d\" = 4.4"
equation "\"mot_front\" = 123"
equation "\"plug_pocket_l\" = 29"
equation "\"hdr_y\" = 68.5"
equation "\"plug_pocket_w\" = 16.6"
equation "\"hdr_z\" = 9.3"
equation "\"plug_pocket_d\" = 2.5"
equation "\"hdr_l\" = 21.2"
equation "\"hdr_w\" = 9.7"
equation "\"brd_xiao_y1\" = 109.5"
equation "\"brd_xiao_y0\" = 88.5"
equation "\"brd_back_clr\" = 1.8"
equation "\"brd_tab_w\" = 6"
equation "\"brd_hole_x1\" = 17.8"
equation "\"brd_hole_x2\" = 4.2"
equation "\"brd_z_front\" = 15.35"
equation "\"brd_pilot_d\" = 1.8"
equation "\"sw_pilot_d\" = 1.8"
equation "\"hole_depth\" = 6"
equation "\"relief_y1\" = 128"
equation "\"relief_z0\" = -5"
equation "\"relief_d\" = 5.5"
equation "\"nose_c\" = 6"
equation "\"nose_hw\" = 7"
equation "\"body_flat_d\" = 5.17"
equation "\"body_ch_d\" = 10.75"
equation "\"body_ch_w\" = 9.78"
equation "\"gusset_h\" = 21.4"
equation "\"col_hw\" = 3.5"
equation "\"seat_screw_z1\" = 13.5"
equation "\"seat_screw_x\" = -5.85"
equation "\"seat_screw_z2\" = -16"
equation "\"ins_z\" = 13.25"
equation "\"ins_top_y\" = 46"
equation "\"ins_bot_y\" = -43"
equation "\"grub_y1\" = 70"
equation "\"grub_y2\" = 108"
equation "\"brd_hole_y\" = 111.8"
equation "\"brd_tab_below\" = 3"
equation "\"sw_pitch\" = 6.5"
equation "\"sw_l\" = 12.8"
equation "\"sw_z0\" = -16"
equation "\"sw_h\" = 6.5"
equation "\"sw_y0\" = 107.7"
equation "\"sw_hole_down\" = 2.9"
body "Solid2"
